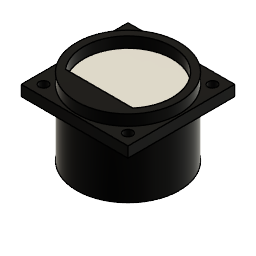
so-45-voltmeter (Autodesk Fusion 360 design; units mm, degrees)
Autodesk Fusion 360 part; units mm, degrees
sketch "Sketch1" plane through (0, 0, 0) normal (0, 1, 0) x (1, 0, 0)
  circle A0 centre (0, 0) radius 22.5
  line L0 (23.4, 23.4) -> (-23.4, 23.4)
  line L1 (-23.4, 23.4) -> (-23.4, -23.4)
  line L2 (-23.4, -23.4) -> (23.4, -23.4)
  line L3 (23.4, -23.4) -> (23.4, 23.4)
  line L4 (23.4, 23.4) -> (-23.4, -23.4) construction
  line L5 (-23.4, 23.4) -> (23.4, -23.4) construction
  line L6 (-18.5, 23.4) -> (-18.5, 18.5) construction
  line L7 (-18.5, -23.4) -> (-18.5, -18.5) construction
  line L8 (-18.5, 18.5) -> (-23.4, 18.5) construction
  line L9 (-18.5, -18.5) -> (-23.4, -18.5) construction
  line L10 (-18.5, 18.5) -> (-18.5, -18.5) construction
  line L11 (0, 23.4) -> (0, 27.1071) construction
  line L12 (18.5, 18.5) -> (18.5, -18.5) construction
  line L13 (18.5, 18.5) -> (23.4, 18.5) construction
  line L14 (-18.5, 18.5) -> (18.5, 18.5) construction
  circle A1 centre (-18.5, 18.5) radius 2
  circle A2 centre (18.5, 18.5) radius 2
  line L15 (23.4, 0) -> (27.4466, 0) construction
  circle A3 centre (-18.5, -18.5) radius 2
  circle A4 centre (18.5, -18.5) radius 2
  circle A5 centre (0, 0) radius 19.4
  line L16 (23.4, -23.4) -> (-23.4, -23.4)
  line L17 (-23.4, -23.4) -> (-23.4, -12.65)
  line L18 (-23.4, -12.65) -> (23.4, -12.65)
  line L19 (23.4, -12.65) -> (23.4, -23.4)
  dimension "d11" = 45
  dimension "d14" = 46.8
  dimension "d15" = 46.8
  dimension "d18" = 37
  dimension "d19" = 37
  dimension "d20" = 4.9
  dimension "d21" = 4.9
  dimension "d22" = 4
  dimension "d23" = -3.1
  dimension "d24" = 10.75
  constraint coincident A0.centre A5.centre
  constraint horizontal L0
  constraint perpendicular L0 L1
  constraint parallel L0 L2
  constraint parallel L1 L3
  constraint coincident L4 A0.centre
  constraint coincident L5 A0.centre
  constraint coincident L0 L6.start
  constraint perpendicular L0 L6
  constraint coincident L2 L7.start
  constraint perpendicular L2 L7
  constraint equal L6 L7
  constraint coincident L1 L8.end
  constraint perpendicular L1 L8
  constraint coincident L1 L9.end
  constraint perpendicular L1 L9
  constraint perpendicular L9 L10
  constraint midpoint L0 L11.start
  constraint perpendicular L0 L11
  constraint symmetric L6.end L11 L12.start
  constraint symmetric L7.end L11 L12.end
  constraint coincident L3 L13.end
  constraint perpendicular L3 L13
  constraint coincident L6.end L8.start
  constraint symmetric L11 A1 A2
  constraint midpoint L3 L15.start
  constraint perpendicular L3 L15
  constraint symmetric A1 L15 A3
  constraint symmetric A2 L15 A4
  constraint horizontal L16
  constraint vertical L17
  constraint horizontal L18
  constraint vertical L19
  measures "d11" diameter of A0
  measures "d14" distance of L1.end L2.end
  measures "d15" distance of L0.end L1.end
  measures "d18" distance of L6.end L7.end
  measures "d19" distance of L6.end L12.start
  measures "d20" distance of L6.end L8.end
  measures "d21" distance of L12.start L13.end
  measures "d22" diameter of A1
  measures "d24" distance of L2.end L18.end
extrude "Extrude1" add sketch "Sketch1" against normal blind 24.4 contours A0 A5 L18 | A0 A5 L18 | A5 L18 | A5 L18 makes body 1
extrude "Extrude2" add sketch "Sketch1" along normal blind 4.65 bodies 1
extrude "Extrude3" add sketch "Sketch1" along normal blind 4.65 from surface at 4.65 contours A0 A5 L18 | A0 A5 L18 | A5 L18 picked at (4.2498, -13.3074) bodies 1
extrude "Extrude4" add sketch "Sketch1" along normal blind 0.8 from surface at 7.4 separate body contours A5 L18 picked at (2.3016, 6.1391) makes body 2
sketch "Sketch2" plane through (0, -24.4, 0) normal (0, -1, 0) x (1, 0, 0)
  circle A0 centre (0, 0) radius 22.5
  line L0 (0, -22.5) -> (0, -12.5) construction
  line L1 (0, -12.5) -> (-9, -12.5) construction
  circle A1 centre (-9, -12.5) radius 1.925
  circle A2 centre (9, -12.5) radius 1.925
  dimension "d34" = 10
  dimension "d35" = 9
  dimension "d36" = 3.85
  constraint coincident A0 L0.start
  constraint vertical L0
  constraint perpendicular L0 L1
  constraint coincident L1.end A1.centre
  constraint symmetric L0 A1 A2
  measures "d34" distance of L0.start L0.end
  measures "d35" distance of L0.end L1.end
  measures "d36" diameter of A1
extrude "Extrude5" add sketch "Sketch2" along normal blind 8.5 separate body contours A1 | A2 makes body 3 at (10.9226, -30.0667, -12.596) makes body 4 at (-7.0774, -30.0667, -12.596)
thread "Thread1" "ISO Metric profile 4.0 M4x0.7 M4x0.7 6g" major diameter 3.908 minor diameter 3.111 pitch 0.7 angle 60 modelled right hand crest width 0.1017 on face at (10.9226, -30.0667, -12.596) crest through (10.954, -24.225, -12.5) on bodies 3
thread "Thread2" "ISO Metric profile 4.0 M4x0.7 M4x0.7 6g" major diameter 3.908 minor diameter 3.111 pitch 0.7 angle 60 modelled right hand crest width 0.1017 on face at (-7.0774, -30.0667, -12.596) crest through (-7.046, -24.225, -12.5) on bodies 4
hidden bodies 2
equation "d11 = voltmeterDiameter"
equation "d14 = voltmeterFaceplateWidth"
equation "d15 = voltmeterFaceplateWidth"
equation "d18 = voltmeterHoleToHole"
equation "d19 = voltmeterHoleToHole"
equation "d34 = voltMeterTopToPin"
equation "d35 = voltmeterPinToPin / 2"
equation "d37 = voltmeterPinHeight"
equation "voltmeterDiameter = 45 mm"
equation "voltmeterFaceplateWidth = 46.8 mm"
equation "voltmeterHoleToHole = 37 mm"
equation "voltmeterPinToPin = 18 mm"
equation "voltMeterTopToPin = 10 mm"
equation "voltmeterPinHeight = 8.5 mm"
